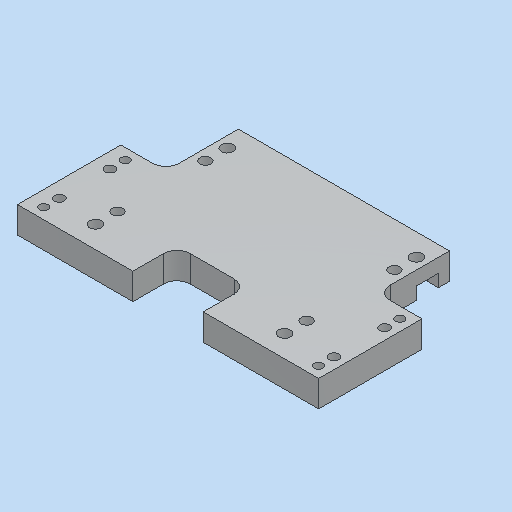
# Autodesk Inventor part: MM0948AN100_G01_105
Saved by Autodesk Inventor 2023.3 (Build 273359000, 359)
## iProperties
Part Number: MM0948AN100_G01_105
Material: 3.3547 AlMg4,5Mn0,7 - AW 5083
Description: =<RBPARTNOTITLE2>
Document SubType Name: Modeling
Designer: ric7an
Mass: 277.127 g
Surface Area: 262.405 cm^2
Volume: 102.64 cm^3
Density: 2.7 g/cm^3
Appearance: Aluminium AnP
Created: 2023-03-23
RBDOCUMENTTYPE: DRF
RBDOCUMENTVERSION: 00
RBDRAWINGMAINSCALE: 1:1
RBDRAWINGMISSINGSPEC: --
RBDRAWINGVOLUME: --
RBGBEDGESIN1: +0,5
RBGBEDGESIN2: +0,2
RBGBEDGESOUT1: -0,3
RBGBEDGESOUT2: -0,1
RBMATERIAL: =<Material>
RBMATMEETS: --
RBMATNO: =<Part Number>
RBPARTMADEOF: 12 x 80 x 137 (FM)
RBPARTNO: SIEHE MNR
RBPARTNOTITLE1: manufactured part
RBPARTNOTITLE2: Anfertigungsteil
RBPARTSAFETYINDICATOR: --
RBSURFACE: anodised colourless
RBSURFACE2: eloxiert farblos
RBZEDGESNORM: ISO13715:2002-06
RBZGENDIMCLASS: m
RBZGENDIMNORM: ISO 2768-1:1989-11
RBZGENGEOCLASS: H
RBZGENGEONORM: ISO 2768-2:1989-11
RBZSURFACENORM: ISO13D2:2002-02
RBZTOLERANCENORM: ISO 14405-1:2010-12
AnP_Material: =<Material>
AnP_TemplVers: 20190222
AnP_Kategorie: 1
MaxAbmaße: 12 x 80 x 137 (FM)
AnP_Kommentar_aktuell: =<Comments>
AnP_Material_aktuell: =<Material>
Author: FH/Wi
Keywords: =<RBPARTMADEOF>
Comments: =<RBSURFACE2>
Revision Number: 01
Autodesk Inventor part; units mm, degrees
ref_plane "YZ Plane" through (0, 0, 0) normal (1, 0, 0) x (0, 1, 0)
ref_plane "XZ Plane" through (0, 0, 0) normal (0, 1, 0) x (-1, 0, 0)
ref_plane "XY Plane" through (0, 0, 0) normal (0, 0, 1) x (1, 0, 0)
sketch "Skizze1" plane through (0, 0, 0) normal (0, 0, 1) x (1, 0, 0)
  line L0 (-68.5, 47) -> (68.5, 47)
  line L1 (68.5, 47) -> (68.5, 0)
  line L2 (68.5, 0) -> (-68.5, 0)
  line L3 (-68.5, 0) -> (-68.5, 47)
  line L4 (0, 96) -> (0, -16) projected
  line L5 (-95.9, 0) -> (95.9, 0) projected
  line L6 (-48, 47) -> (48, 47)
  line L7 (48, 47) -> (48, 80)
  line L8 (48, 80) -> (-48, 80)
  line L9 (-48, 80) -> (-48, 47)
  point P0 (0, 0)
  dimension "d0" = 137
  dimension "d1" = 47
  dimension "d4" = 96
  dimension "d6" = 80
  constraints: 16 end point, 4 parallel, 2 horizontal, 2 perpendicular, 1 collinear, 1 point on line, 2 other
  measures "d0" distance of L0.start L0.end
  measures "d1" distance of L0.end L1.end
  measures "d4" distance of L7.end L8.end
  measures "d6" distance between parallel lines of L5 L8
extrude "Extrusion1" add sketch "Skizze1" along normal blind 12
sketch "Skizze2" plane through (0, 0, 0) normal (0, 0, 1) x (1, 0, 0)
  line L0 (0, 96) -> (0, -16) projected
  line L1 (-95.9, 0) -> (95.9, 0) projected
  point P0 (0, 0)
  point P1 (-43, 70)
  point P2 (-43, 10)
  point P3 (43, 10)
  point P4 (43, 70)
  dimension "d7" = 86
  dimension "d8" = 60
  dimension "d9" = 10
  constraints: 2 symmetric about line, 1 vertical alignment
  measures "d7" distance of point (43, 10) point (-43, 10)
  measures "d8" distance of point (-43, 70) point (-43, 10)
  measures "d9" distance from line of L1 point (-43, 10)
hole "Bohrung1" at (-43, 70, 0) at (-43, 10, 0) at (43, 10, 0) at (43, 70, 0) direction (0, 0, 1) diameter 5.5 end through all counterbore diameter 10 counterbore depth 5.7 clearance for "Inbusschraube ISO 4762  versenkt" size "M5" standard "ISO"
sketch "Skizze3" plane through (0, 0, 0) normal (0, 0, -1) x (-1, 0, 0)
  line L0 (0, -16) -> (0, 96) projected
  line L1 (-95.9, 0) -> (95.9, 0) projected
  point P0 (0, 0)
  point P1 (61.5, 41)
  point P2 (61.5, 35)
  point P3 (61.5, 12)
  point P4 (61.5, 6)
  point P5 (-63.5, 41)
  point P6 (-63.5, 35)
  point P7 (-63.5, 12)
  point P8 (-63.5, 6)
  dimension "d17" = 35
  dimension "d19" = 6
  dimension "d20" = 6
  dimension "d29" = 61.5
  dimension "d35" = 6
  dimension "d36" = 63.5
  constraints: 6 vertical alignment, 4 horizontal alignment
  measures "d17" distance of point (61.5, 6) point (61.5, 41)
  measures "d19" distance of point (61.5, 6) point (61.5, 12)
  measures "d20" distance from line of L1 point (61.5, 6)
  measures "d29" distance from line of point (61.5, 6) L0
  measures "d35" distance of point (61.5, 35) point (61.5, 41)
  measures "d36" distance from line of L0 point (-63.5, 6)
hole "Bohrung2" at (-61.5, 35, 0) at (-61.5, 12, 0) at (63.5, 35, 0) at (63.5, 12, 0) direction (0, 0, 1) diameter 4.5 end through all counterbore diameter 8 counterbore depth 4.6 clearance for "Inbusschraube ISO 4762  versenkt" size "M4" standard "ISO"
sketch "Skizze4" plane through (0, 0, 12) normal (0, 0, 1) x (1, 0, 0)
  circle A0 centre (63.5, 35) radius 2.25 projected
  circle A1 centre (-61.5, 35) radius 2.25 projected
  circle A2 centre (-61.5, 12) radius 2.25 projected
  circle A3 centre (63.5, 12) radius 2.25 projected
  line L0 (48, 47) -> (48, 80) projected
  line L1 (48, 80) -> (-48, 80) projected
  line L2 (-48, 80) -> (-48, 47) projected
  line L3 (-48, 47) -> (-68.5, 47) projected
  line L4 (-68.5, 47) -> (-68.5, 0) projected
  line L5 (-68.5, 0) -> (68.5, 0) projected
  line L6 (68.5, 0) -> (68.5, 47) projected
  line L7 (68.5, 47) -> (48, 47) projected
  line L8 (16, 0) -> (-16, 0)
  line L9 (-16, 0) -> (-16, 20)
  line L10 (-16, 20) -> (16, 20)
  line L11 (16, 20) -> (16, 0)
  line L12 (0, 204) -> (0, -34) projected
  line L13 (-95.9, 0) -> (95.9, 0) projected
  point P0 (0, 0)
  dimension "d0" = 137
  dimension "d31" = 32
  dimension "d32" = 20
  constraints: 8 end point, 2 parallel, 1 horizontal, 1 perpendicular, 1 point on line, 1 other
  measures "d31" distance of L9.end L10.end
  measures "d32" distance of L10.end L8.start
extrude "Extrusion2" cut sketch "Skizze4" against normal through all contours L12 L5 L9 L10 | L10 L11 L5 L12
fillet "Rundung1" radius 6 4 edges at (-16, 20, 6) (16, 20, 6) (-48, 47, 6) (48, 47, 6)
sketch "Skizze5" plane through (0, 0, 12) normal (0, 0, 1) x (1, 0, 0)
  circle A0 centre (-61.5, 35) radius 2.25 projected
  circle A1 centre (63.5, 35) radius 2.25 projected
  circle A2 centre (-61.5, 12) radius 2.25 projected
  circle A3 centre (63.5, 12) radius 2.25 projected
  point P0 (0, 0)
  point P1 (-61.5, 42)
  point P2 (-61.5, 5)
  point P3 (63.5, 42)
  point P4 (63.5, 5)
  dimension "d38" = 7
  dimension "d39" = 7
  dimension "d40" = 7
  dimension "d41" = 7
  constraints: 4 vertical alignment
  measures "d38" distance of A0.centre point (-61.5, 42)
  measures "d39" distance of point (-61.5, 5) A2.centre
  measures "d40" distance of A1.centre point (63.5, 42)
  measures "d41" distance of point (63.5, 5) A3.centre
hole "Bohrung3" at (-61.5, 42, 12) at (-61.5, 5, 12) at (63.5, 42, 12) at (63.5, 5, 12) direction (0, 0, -1) diameter 4 end through all
sketch "Skizze6" plane through (0, 0, 0) normal (0, 0, -1) x (-1, 0, 0)
  circle A0 centre (-43, 70) radius 5 projected
  circle A1 centre (43, 70) radius 5 projected
  circle A2 centre (-63.5, 42) radius 2 projected
  circle A3 centre (61.5, 42) radius 2 projected
  circle A4 centre (61.5, 5) radius 2 projected
  circle A5 centre (-63.5, 5) radius 2 projected
  line L0 (16, 14) -> (16, 0) projected
  line L1 (16, 0) -> (68.5, 0) projected
  line L2 (68.5, 0) -> (68.5, 47) projected
  line L3 (68.5, 47) -> (54, 47) projected
  arc A6 (48, 53) -> (54, 47) centre (54, 53) ccw projected
  line L4 (48, 70) -> (48, 53) projected
  circle A7 centre (43, 70) radius 5 projected
  line L5 (48, 80) -> (48, 70) projected
  line L6 (-48, 80) -> (48, 80) projected
  line L7 (-48, 70) -> (-48, 80) projected
  circle A8 centre (-43, 70) radius 5 projected
  line L8 (-48, 53) -> (-48, 70) projected
  arc A9 (-54, 47) -> (-48, 53) centre (-54, 53) ccw projected
  line L9 (-54, 47) -> (-68.5, 47) projected
  line L10 (-68.5, 47) -> (-68.5, 0) projected
  line L11 (-68.5, 0) -> (-16, 0) projected
  line L12 (-16, 0) -> (-16, 14) projected
  arc A10 (-10, 20) -> (-16, 14) centre (-10, 14) ccw projected
  line L13 (-10, 20) -> (10, 20) projected
  arc A11 (16, 14) -> (10, 20) centre (10, 14) ccw projected
  circle A12 centre (-63.5, 35) radius 4 projected
  circle A13 centre (61.5, 35) radius 4 projected
  circle A14 centre (61.5, 12) radius 4 projected
  circle A15 centre (-63.5, 12) radius 4 projected
  circle A16 centre (43, 10) radius 5 projected
  circle A17 centre (-43, 10) radius 5 projected
  line L14 (-48, 75) -> (-43, 75)
  line L15 (-43, 75) -> (-43, 65)
  line L16 (-43, 65) -> (-48, 65)
  line L17 (-48, 65) -> (-48, 75)
  line L18 (48, 65) -> (43, 65)
  line L19 (43, 65) -> (43, 75)
  line L20 (43, 75) -> (48, 75)
  line L21 (48, 75) -> (48, 65)
  point P0 (0, 0)
  constraints: 16 end point, 6 horizontal, 4 horizontal alignment, 4 parallel, 3 midpoint, 2 perpendicular, 1 point on line
extrude "Extrusion3" cut sketch "Skizze6" against normal up to surface (5.7 mm away) contours L15 A0 | A0 L7 L14 | L16 L8 A0 | L5 A1 L20 | A1 L19 | L4 L18 A1 picked at (-46.0712, 70.3709) picked at (43.7231, 68.4984)
sketch "Skizze7" plane through (0, 0, 12) normal (0, 0, 1) x (1, 0, 0)
  line L0 (-68.5, 0) -> (-16, 0) projected
  circle A0 centre (63.5, 42) radius 2 projected
  circle A1 centre (-61.5, 42) radius 2 projected
  circle A2 centre (-61.5, 5) radius 2 projected
  circle A3 centre (63.5, 5) radius 2 projected
  line L1 (-16, 0) -> (-16, 14) projected
  arc A4 (-10, 20) -> (-16, 14) centre (-10, 14) ccw projected
  line L2 (-10, 20) -> (10, 20) projected
  arc A5 (16, 14) -> (10, 20) centre (10, 14) ccw projected
  line L3 (16, 14) -> (16, 0) projected
  line L4 (16, 0) -> (68.5, 0) projected
  line L5 (68.5, 0) -> (68.5, 47) projected
  line L6 (68.5, 47) -> (54, 47) projected
  arc A6 (48, 53) -> (54, 47) centre (54, 53) ccw projected
  line L7 (48, 53) -> (48, 80) projected
  line L8 (48, 80) -> (-48, 80) projected
  line L9 (-48, 80) -> (-48, 53) projected
  arc A7 (-54, 47) -> (-48, 53) centre (-54, 53) ccw projected
  line L10 (-54, 47) -> (-68.5, 47) projected
  line L11 (-68.5, 47) -> (-68.5, 0) projected
  line L12 (-68.5, 0) -> (-16, 0) projected
  circle A8 centre (43, 70) radius 2.75 projected
  circle A9 centre (-43, 10) radius 2.75 projected
  circle A10 centre (-43, 70) radius 2.75 projected
  circle A11 centre (43, 10) radius 2.75 projected
  circle A12 centre (63.5, 12) radius 2.25 projected
  circle A13 centre (-61.5, 12) radius 2.25 projected
  circle A14 centre (-61.5, 35) radius 2.25 projected
  circle A15 centre (63.5, 35) radius 2.25 projected
  point P0 (0, 0)
  point P1 (-43, 20)
  point P2 (43, 20)
  point P3 (-43, 60)
  point P4 (43, 60)
  dimension "d51" = 20
  dimension "d59" = 60
  constraints: 4 vertical alignment, 2 horizontal alignment
  measures "d51" distance from line of L0 point (-43, 20)
  measures "d59" distance from line of point (-43, 60) L0
hole "Bohrung4" at (-43, 20, 12) at (43, 20, 12) at (-43, 60, 12) at (43, 60, 12) direction (0, 0, -1) diameter 5 depth 10 tip angle 118
equation "\"d19\" = d35"
equation "\"d39\" = d38"
equation "\"d40\" = d38"
equation "\"d41\" = d38"
